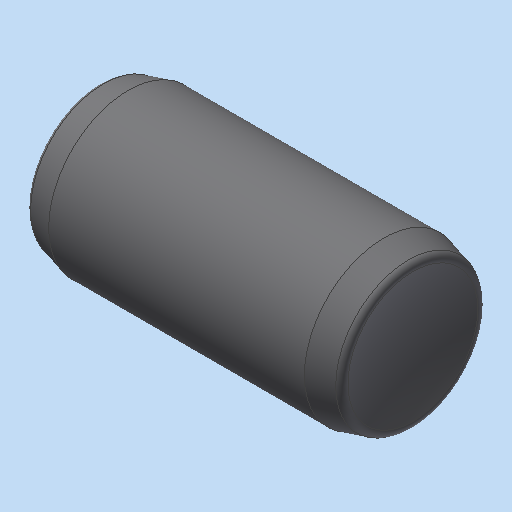
# Autodesk Inventor part: Zylinderstift_DIN_EN_ISO_8734___5x10
Saved by Autodesk Inventor 2023.3 (Build 273359000, 359)
## iProperties
Shininess: 64.0
Length Units: 11269
Angle Units: 11279
Time Units: 11290
Mass Units: 11283
Length Display Precision: 3
Angle Display Precision: 2
Compacted: True
Part Number: Zylinderstift_DIN_EN_ISO_8734___5x10
Document SubType Name: Modeling
Created: 2004-04-23
Description: =<RBPARTNOTITLE2>
Vendor: NORM8
Designer: C.Fischer
Manufacturer: Standard
Standards Organization: Custom
Density: 7.85 g/cm^3
Material: xStahl_AnP_Dummymaterial
Mass: 1.45975 g
Surface Area: 1.86113 cm^2
Volume: 0.185956 cm^3
Appearance: Stahl - normal AnP
DOC_ID: 5 F45 Zylinderstift_DIN_EN_ISO_8734___5x12
GAIN_REFID: 20__Zylinderstift_DIN_EN_ISO_8734___5x12:81C07
Control State: 0
Master: False
Checked Out: False
CNS_NB: Zylinderstift DIN EN ISO 8734 - 5x10
CNS_NN: DIN EN ISO 8734
CNS_NT: Zylinderstifte, aus gehaertetem Stahl und martensitischem nichtrostendem Stahl
CNS_NBSYN: Zylinderstift DIN EN ISO 8734 - $NENN.
CNS_LINA: Zylinderstift DIN EN ISO 8734 - 5x10
CNS_D: 5.000
CNS_L: 10
CNS_A: 0.980
CNS_NENN: 5x10
CNS_KT: DUMMY
PSOL_IDENT_0: {C:\partsolutions\data\23d-libs\bosch_bamberg\stifte\scherstifte\din_en_iso_8734.prj},164 {VTYP=3D},
PSOL_IDENT_1: {NB=Zylinderstift DIN EN ISO 8734 - 5x12},{NN=DIN EN ISO 8734},{DATE=26.11.2003},{GEOMDATE=26.11.200
PSOL_IDENT_2: 3},{VERSION=v1},{LINEID=600},{LINESUBID=-1},{WBVAR=}  {NB=Zylinderstift DIN EN ISO 8734 - 5x12},{LIN
PSOL_IDENT_3: A=Zylinderstift DIN EN ISO 8734 - 5x12},{KT=DUMMY},{IDNR=},{D=5.000},{L=12.000},{A=0.980},{NENN=5x12
PSOL_IDENT_4: }
DEF_STKID: T21187
Bezeichnung1: Zylinderstift DIN EN ISO 8734 - 5x10
Bezeichnung2: Zylinderstifte, aus gehaertetem Stahl u
RBPARTNOTITLE1: Parallel pins of hardened and martensitic stainless steel
RBPARTNOTITLE2: Zylinderstifte, aus gehaertetem Stahl und martensitischem nichtrostendem Stahl
RBDRAWINGMISSINGSPEC: --
AnP_Kategorie: 4
RBPARTMADEOF: ISO 8734 - 5x10 - A - St
Density: 0.0
Volumn: 0.0
Area: 0.0
PropertySet Name: Model Information
Title: Zylinderstift DIN EN ISO 8734 - 5x10
Author: C.Fischer
Keywords: =<RBPARTMADEOF>
Comments: =<RBSURFACE2>
Revision Number: 01
Autodesk Inventor part; units mm, degrees
sketch "Sketch_1" plane through (0, 0, 0) normal (0, 0, 1) x (1, 0, 0)
  line L0 (9.608, 0) -> (0, 0)
  arc A0 (0.392, 0) -> (0.0673, 2.0417) centre (-6.1892, 0) ccw
  arc A1 (0.2029, 2.2918) -> (0.0673, 2.0417) centre (0.2536, 2.1025) ccw
  line L1 (0.2029, 2.2918) -> (0.98, 2.5)
  line L2 (0.98, 2.5) -> (9.02, 2.5)
  line L3 (9.02, 2.5) -> (9.7971, 2.2918)
  arc A2 (9.9327, 2.0417) -> (9.7971, 2.2918) centre (9.7464, 2.1025) ccw
  arc A3 (9.9327, 2.0417) -> (9.608, 0) centre (16.1892, 0) ccw
  line L4 (9.608, 0) -> (0.392, 0)
  constraints: 10 end point, 8 point on circle, 4 centre point, 9 other
revolve "Revolution1" add sketch "Sketch_1" angle 360 about axis through (9.608, 0, 0) along (1, 0, 0)
ref_plane "IP2_XY" through (0, 0, 0) normal (1, 0, 0) x (0, 0, -1)
ref_plane "IP2_YZ" through (0, 0, 0) normal (0, 0, -1) x (0, 1, 0)
ref_plane "IP1_XY" through (6, 0, 0) normal (1, 0, 0) x (0, 0, -1)
ref_plane "IP1_YZ" through (6, 0, 0) normal (0, 0, -1) x (0, 1, 0)
ref_plane "IP3_XY" through (12, 0, 0) normal (1, 0, 0) x (0, 0, -1)
ref_plane "IP3_YZ" through (12, 0, 0) normal (0, 0, -1) x (0, 1, 0)
